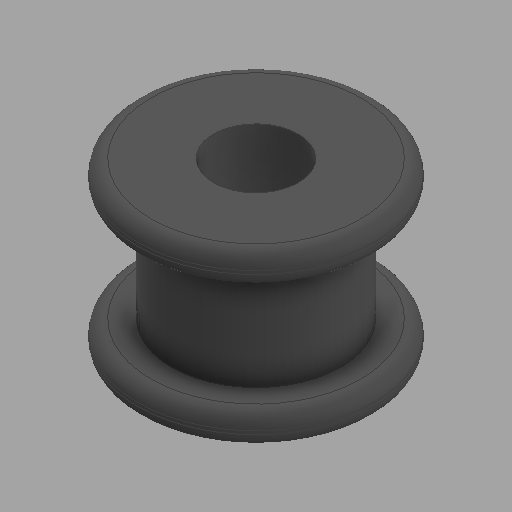
# Autodesk Inventor part: grommet
Saved by Autodesk Inventor 2025 (Build 290162000, 162)
## iProperties
Created: 2024-11-09
Part Number: grommet
Material: 일반
Document SubType Name: Modeling
Designer: OSB
Density: 1 g/cm^3
Appearance: 기본값
Author: OSB
Autodesk Inventor part; units mm, degrees
ref_plane "YZ Plane" through (0, 0, 0) normal (1, 0, 0) x (0, 1, 0)
ref_plane "XZ Plane" through (0, 0, 0) normal (0, 1, 0) x (-1, 0, 0)
ref_plane "XY Plane" through (0, 0, 0) normal (0, 0, 1) x (1, 0, 0)
sketch "스케치1" plane through (0, 0, 0) normal (0, 0, 1) x (1, 0, 0)
  circle A0 centre (0, 0) radius 3.5
  circle A1 centre (0, 0) radius 1.25
  circle A2 centre (0, 0) radius 2.5
  dimension "d0" = 7
  dimension "d1" = 2.5
  dimension "d2" = 5
  constraints: 3 centre point, 3 coincident
  measures "d0" diameter of A0
  measures "d1" diameter of A1
  measures "d2" diameter of A2
extrude "돌출1" add sketch "스케치1" along normal mid plane 5 contours A0 | A2
extrude "돌출2" cut sketch "스케치1" along normal mid plane 3.2 contours A0
fillet "모깎기1" radius 0.4 4 edges at (-3.5, 0, 2.5) (-3.5, 0, 1.6) (-3.5, 0, -1.6) (-3.5, 0, -2.5)
